Autodesk Fusion 360 part; units mm, degrees
(part 2 of 3)
ref_plane "WorkPlane125" through (0, 0, 11) normal (0, 0, 1) x (1, 0, 0)
sketch "magnet_N_st4_a3_d0" plane through (0, 0, 11) normal (0, 0, 1) x (1, 0, 0)
  line L0 (80.2, 10) -> (99.8, 10)
  line L1 (99.8, 10) -> (99.8, 20)
  line L2 (99.8, 20) -> (80.2, 20)
  line L3 (80.2, 20) -> (80.2, 10)
extrude "Extrude85" add sketch "magnet_N_st4_a3_d0" along normal mid plane 5 separate body makes body 105
ref_plane "WorkPlane126" through (0, 0, 16) normal (0, 0, 1) x (1, 0, 0)
sketch "magnet_N_st4_a3_d1" plane through (0, 0, 16) normal (0, 0, 1) x (1, 0, 0)
  line L0 (80.2, 10) -> (99.8, 10)
  line L1 (99.8, 10) -> (99.8, 20)
  line L2 (99.8, 20) -> (80.2, 20)
  line L3 (80.2, 20) -> (80.2, 10)
extrude "Extrude86" add sketch "magnet_N_st4_a3_d1" along normal mid plane 5 separate body makes body 106
ref_plane "WorkPlane127" through (0, 0, -11) normal (0, 0, 1) x (1, 0, 0)
sketch "magnet_S_st4_a3_d0" plane through (0, 0, -11) normal (0, 0, 1) x (1, 0, 0)
  line L0 (80.2, 10) -> (99.8, 10)
  line L1 (99.8, 10) -> (99.8, 20)
  line L2 (99.8, 20) -> (80.2, 20)
  line L3 (80.2, 20) -> (80.2, 10)
extrude "Extrude87" add sketch "magnet_S_st4_a3_d0" along normal mid plane 5 separate body makes body 107
ref_plane "WorkPlane128" through (0, 0, -16) normal (0, 0, 1) x (1, 0, 0)
sketch "magnet_S_st4_a3_d1" plane through (0, 0, -16) normal (0, 0, 1) x (1, 0, 0)
  line L0 (80.2, 10) -> (99.8, 10)
  line L1 (99.8, 10) -> (99.8, 20)
  line L2 (99.8, 20) -> (80.2, 20)
  line L3 (80.2, 20) -> (80.2, 10)
extrude "Extrude88" add sketch "magnet_S_st4_a3_d1" along normal mid plane 5 separate body makes body 108
ref_plane "WorkPlane129" through (0, 0, 11) normal (0, 0, 1) x (1, 0, 0)
sketch "magnet_N_st5_a0_d0" plane through (0, 0, 11) normal (0, 0, 1) x (1, 0, 0)
  line L0 (100.2, -20) -> (119.8, -20)
  line L1 (119.8, -20) -> (119.8, -10)
  line L2 (119.8, -10) -> (100.2, -10)
  line L3 (100.2, -10) -> (100.2, -20)
extrude "Extrude89" add sketch "magnet_N_st5_a0_d0" along normal mid plane 5 separate body makes body 109
ref_plane "WorkPlane130" through (0, 0, 16) normal (0, 0, 1) x (1, 0, 0)
sketch "magnet_N_st5_a0_d1" plane through (0, 0, 16) normal (0, 0, 1) x (1, 0, 0)
  line L0 (100.2, -20) -> (119.8, -20)
  line L1 (119.8, -20) -> (119.8, -10)
  line L2 (119.8, -10) -> (100.2, -10)
  line L3 (100.2, -10) -> (100.2, -20)
extrude "Extrude90" add sketch "magnet_N_st5_a0_d1" along normal mid plane 5 separate body makes body 110
ref_plane "WorkPlane131" through (0, 0, -11) normal (0, 0, 1) x (1, 0, 0)
sketch "magnet_S_st5_a0_d0" plane through (0, 0, -11) normal (0, 0, 1) x (1, 0, 0)
  line L0 (100.2, -20) -> (119.8, -20)
  line L1 (119.8, -20) -> (119.8, -10)
  line L2 (119.8, -10) -> (100.2, -10)
  line L3 (100.2, -10) -> (100.2, -20)
extrude "Extrude91" add sketch "magnet_S_st5_a0_d0" along normal mid plane 5 separate body makes body 111
ref_plane "WorkPlane132" through (0, 0, -16) normal (0, 0, 1) x (1, 0, 0)
sketch "magnet_S_st5_a0_d1" plane through (0, 0, -16) normal (0, 0, 1) x (1, 0, 0)
  line L0 (100.2, -20) -> (119.8, -20)
  line L1 (119.8, -20) -> (119.8, -10)
  line L2 (119.8, -10) -> (100.2, -10)
  line L3 (100.2, -10) -> (100.2, -20)
extrude "Extrude92" add sketch "magnet_S_st5_a0_d1" along normal mid plane 5 separate body makes body 112
ref_plane "WorkPlane133" through (0, 0, 11) normal (0, 0, 1) x (1, 0, 0)
sketch "magnet_N_st5_a1_d0" plane through (0, 0, 11) normal (0, 0, 1) x (1, 0, 0)
  line L0 (100.2, -10) -> (119.8, -10)
  line L1 (119.8, -10) -> (119.8, 0)
  line L2 (119.8, 0) -> (100.2, 0)
  line L3 (100.2, 0) -> (100.2, -10)
extrude "Extrude93" add sketch "magnet_N_st5_a1_d0" along normal mid plane 5 separate body makes body 113
ref_plane "WorkPlane134" through (0, 0, 16) normal (0, 0, 1) x (1, 0, 0)
sketch "magnet_N_st5_a1_d1" plane through (0, 0, 16) normal (0, 0, 1) x (1, 0, 0)
  line L0 (100.2, -10) -> (119.8, -10)
  line L1 (119.8, -10) -> (119.8, 0)
  line L2 (119.8, 0) -> (100.2, 0)
  line L3 (100.2, 0) -> (100.2, -10)
extrude "Extrude94" add sketch "magnet_N_st5_a1_d1" along normal mid plane 5 separate body makes body 114
ref_plane "WorkPlane135" through (0, 0, -11) normal (0, 0, 1) x (1, 0, 0)
sketch "magnet_S_st5_a1_d0" plane through (0, 0, -11) normal (0, 0, 1) x (1, 0, 0)
  line L0 (100.2, -10) -> (119.8, -10)
  line L1 (119.8, -10) -> (119.8, 0)
  line L2 (119.8, 0) -> (100.2, 0)
  line L3 (100.2, 0) -> (100.2, -10)
extrude "Extrude95" add sketch "magnet_S_st5_a1_d0" along normal mid plane 5 separate body makes body 115
ref_plane "WorkPlane136" through (0, 0, -16) normal (0, 0, 1) x (1, 0, 0)
sketch "magnet_S_st5_a1_d1" plane through (0, 0, -16) normal (0, 0, 1) x (1, 0, 0)
  line L0 (100.2, -10) -> (119.8, -10)
  line L1 (119.8, -10) -> (119.8, 0)
  line L2 (119.8, 0) -> (100.2, 0)
  line L3 (100.2, 0) -> (100.2, -10)
extrude "Extrude96" add sketch "magnet_S_st5_a1_d1" along normal mid plane 5 separate body makes body 116
ref_plane "WorkPlane137" through (0, 0, 11) normal (0, 0, 1) x (1, 0, 0)
sketch "magnet_N_st5_a2_d0" plane through (0, 0, 11) normal (0, 0, 1) x (1, 0, 0)
  line L0 (100.2, 0) -> (119.8, 0)
  line L1 (119.8, 0) -> (119.8, 10)
  line L2 (119.8, 10) -> (100.2, 10)
  line L3 (100.2, 10) -> (100.2, 0)
extrude "Extrude97" add sketch "magnet_N_st5_a2_d0" along normal mid plane 5 separate body makes body 117
ref_plane "WorkPlane138" through (0, 0, 16) normal (0, 0, 1) x (1, 0, 0)
sketch "magnet_N_st5_a2_d1" plane through (0, 0, 16) normal (0, 0, 1) x (1, 0, 0)
  line L0 (100.2, 0) -> (119.8, 0)
  line L1 (119.8, 0) -> (119.8, 10)
  line L2 (119.8, 10) -> (100.2, 10)
  line L3 (100.2, 10) -> (100.2, 0)
extrude "Extrude98" add sketch "magnet_N_st5_a2_d1" along normal mid plane 5 separate body makes body 118
ref_plane "WorkPlane139" through (0, 0, -11) normal (0, 0, 1) x (1, 0, 0)
sketch "magnet_S_st5_a2_d0" plane through (0, 0, -11) normal (0, 0, 1) x (1, 0, 0)
  line L0 (100.2, 0) -> (119.8, 0)
  line L1 (119.8, 0) -> (119.8, 10)
  line L2 (119.8, 10) -> (100.2, 10)
  line L3 (100.2, 10) -> (100.2, 0)
extrude "Extrude99" add sketch "magnet_S_st5_a2_d0" along normal mid plane 5 separate body makes body 119
ref_plane "WorkPlane140" through (0, 0, -16) normal (0, 0, 1) x (1, 0, 0)
sketch "magnet_S_st5_a2_d1" plane through (0, 0, -16) normal (0, 0, 1) x (1, 0, 0)
  line L0 (100.2, 0) -> (119.8, 0)
  line L1 (119.8, 0) -> (119.8, 10)
  line L2 (119.8, 10) -> (100.2, 10)
  line L3 (100.2, 10) -> (100.2, 0)
extrude "Extrude100" add sketch "magnet_S_st5_a2_d1" along normal mid plane 5 separate body makes body 120
ref_plane "WorkPlane141" through (0, 0, 11) normal (0, 0, 1) x (1, 0, 0)
sketch "magnet_N_st5_a3_d0" plane through (0, 0, 11) normal (0, 0, 1) x (1, 0, 0)
  line L0 (100.2, 10) -> (119.8, 10)
  line L1 (119.8, 10) -> (119.8, 20)
  line L2 (119.8, 20) -> (100.2, 20)
  line L3 (100.2, 20) -> (100.2, 10)
extrude "Extrude101" add sketch "magnet_N_st5_a3_d0" along normal mid plane 5 separate body makes body 121
ref_plane "WorkPlane142" through (0, 0, 16) normal (0, 0, 1) x (1, 0, 0)
sketch "magnet_N_st5_a3_d1" plane through (0, 0, 16) normal (0, 0, 1) x (1, 0, 0)
  line L0 (100.2, 10) -> (119.8, 10)
  line L1 (119.8, 10) -> (119.8, 20)
  line L2 (119.8, 20) -> (100.2, 20)
  line L3 (100.2, 20) -> (100.2, 10)
extrude "Extrude102" add sketch "magnet_N_st5_a3_d1" along normal mid plane 5 separate body makes body 122
ref_plane "WorkPlane143" through (0, 0, -11) normal (0, 0, 1) x (1, 0, 0)
sketch "magnet_S_st5_a3_d0" plane through (0, 0, -11) normal (0, 0, 1) x (1, 0, 0)
  line L0 (100.2, 10) -> (119.8, 10)
  line L1 (119.8, 10) -> (119.8, 20)
  line L2 (119.8, 20) -> (100.2, 20)
  line L3 (100.2, 20) -> (100.2, 10)
extrude "Extrude103" add sketch "magnet_S_st5_a3_d0" along normal mid plane 5 separate body makes body 123
ref_plane "WorkPlane144" through (0, 0, -16) normal (0, 0, 1) x (1, 0, 0)
sketch "magnet_S_st5_a3_d1" plane through (0, 0, -16) normal (0, 0, 1) x (1, 0, 0)
  line L0 (100.2, 10) -> (119.8, 10)
  line L1 (119.8, 10) -> (119.8, 20)
  line L2 (119.8, 20) -> (100.2, 20)
  line L3 (100.2, 20) -> (100.2, 10)
extrude "Extrude104" add sketch "magnet_S_st5_a3_d1" along normal mid plane 5 separate body makes body 124
ref_plane "WorkPlane145" through (0, 0, 19.5) normal (0, 0, 1) x (1, 0, 0)
sketch "hood_top" plane through (0, 0, 19.5) normal (0, 0, 1) x (1, 0, 0)
  line L0 (-1, -26) -> (121, -26)
  line L1 (121, -26) -> (121, 26)
  line L2 (121, 26) -> (-1, 26)
  line L3 (-1, 26) -> (-1, -26)
extrude "Extrude105" add sketch "hood_top" along normal mid plane 2 separate body makes body 125
ref_plane "WorkPlane146" through (0, 0, -19.5) normal (0, 0, 1) x (1, 0, 0)
sketch "hood_bottom" plane through (0, 0, -19.5) normal (0, 0, 1) x (1, 0, 0)
  line L0 (-1, -26) -> (121, -26)
  line L1 (121, -26) -> (121, 26)
  line L2 (121, 26) -> (-1, 26)
  line L3 (-1, 26) -> (-1, -26)
extrude "Extrude106" add sketch "hood_bottom" along normal mid plane 2 separate body makes body 126
ref_plane "WorkPlane147" through (0, 24.5, 0) normal (0, 1, 0) x (0, 0, 1)
sketch "endbar_rear_p" plane through (0, 24.5, 0) normal (0, 1, 0) x (1, 0, 0)
  line L0 (118, -18.5) -> (120, -18.5)
  line L1 (120, -18.5) -> (120, 18.5)
  line L2 (120, 18.5) -> (118, 18.5)
  line L3 (118, 18.5) -> (118, -18.5)
extrude "Extrude107" add sketch "endbar_rear_p" along normal mid plane 2 separate body makes body 127
ref_plane "WorkPlane148" through (0, -24.5, 0) normal (0, 1, 0) x (0, 0, 1)
sketch "endbar_rear_n" plane through (0, -24.5, 0) normal (0, 1, 0) x (1, 0, 0)
  line L0 (118, -18.5) -> (120, -18.5)
  line L1 (120, -18.5) -> (120, 18.5)
  line L2 (120, 18.5) -> (118, 18.5)
  line L3 (118, 18.5) -> (118, -18.5)
extrude "Extrude108" add sketch "endbar_rear_n" along normal mid plane 2 separate body makes body 128
ref_plane "WorkPlane149" through (-30, 0, 0) normal (1, 0, 0) x (0, 1, 0)
sketch "Sketch149" plane through (-30, 0, 0) normal (1, 0, 0) x (0, 0, -1)
  line L0 (-12.2, -25.2) -> (-11, -25.2)
  line L1 (-11, -25.2) -> (-11, 25.2)
  line L2 (-11, 25.2) -> (-12.2, 25.2)
  line L3 (-12.2, 25.2) -> (-12.2, -25.2)
ref_plane "WorkPlane150" through (-23.6, 0, 0) normal (1, 0, 0) x (0, 1, 0)
sketch "Sketch150" plane through (-23.6, 0, 0) normal (1, 0, 0) x (0, 0, -1)
  line L0 (-17.346, -29.146) -> (-13.8, -29.146)
  line L1 (-13.8, -29.146) -> (-13.8, 29.146)
  line L2 (-13.8, 29.146) -> (-17.346, 29.146)
  line L3 (-17.346, 29.146) -> (-17.346, -29.146)
loft "Loft21" add profiles "Sketch149", "Sketch150" section 1 section 2 separate body makes body 129
ref_plane "WorkPlane151" through (-24.4, 0, 0) normal (1, 0, 0) x (0, 1, 0)
sketch "Sketch151" plane through (-24.4, 0, 0) normal (1, 0, 0) x (0, 0, -1)
  line L0 (-16.8608, -28.8108) -> (-13.45, -28.8108)
  line L1 (-13.45, -28.8108) -> (-13.45, 28.8108)
  line L2 (-13.45, 28.8108) -> (-16.8608, 28.8108)
  line L3 (-16.8608, 28.8108) -> (-16.8608, -28.8108)
ref_plane "WorkPlane152" through (-21.6, 0, 0) normal (1, 0, 0) x (0, 1, 0)
sketch "Sketch152" plane through (-21.6, 0, 0) normal (1, 0, 0) x (0, 0, -1)
  line L0 (-18.4462, -29.8371) -> (-14.6091, -29.8371)
  line L1 (-14.6091, -29.8371) -> (-14.6091, 29.8371)
  line L2 (-14.6091, 29.8371) -> (-18.4462, 29.8371)
  line L3 (-18.4462, 29.8371) -> (-18.4462, -29.8371)
loft "Loft22" add profiles "Sketch151", "Sketch152" section 1 section 2 separate body makes body 130
ref_plane "WorkPlane153" through (-22.4, 0, 0) normal (1, 0, 0) x (0, 1, 0)
sketch "Sketch153" plane through (-22.4, 0, 0) normal (1, 0, 0) x (0, 0, -1)
  line L0 (-18.0528, -29.6278) -> (-14.325, -29.6278)
  line L1 (-14.325, -29.6278) -> (-14.325, 29.6278)
  line L2 (-14.325, 29.6278) -> (-18.0528, 29.6278)
  line L3 (-18.0528, 29.6278) -> (-18.0528, -29.6278)
ref_plane "WorkPlane154" through (-17.6, 0, 0) normal (1, 0, 0) x (0, 1, 0)
sketch "Sketch154" plane through (-17.6, 0, 0) normal (1, 0, 0) x (0, 0, -1)
  line L0 (-19.9773, -30.2773) -> (-15.7, -30.2773)
  line L1 (-15.7, -30.2773) -> (-15.7, 30.2773)
  line L2 (-15.7, 30.2773) -> (-19.9773, 30.2773)
  line L3 (-19.9773, 30.2773) -> (-19.9773, -30.2773)
loft "Loft23" add profiles "Sketch153", "Sketch154" section 1 section 2 separate body makes body 131
ref_plane "WorkPlane155" through (-18.4, 0, 0) normal (1, 0, 0) x (0, 1, 0)
sketch "Sketch155" plane through (-18.4, 0, 0) normal (1, 0, 0) x (0, 0, -1)
  line L0 (-19.6832, -30.2013) -> (-15.4818, -30.2013)
  line L1 (-15.4818, -30.2013) -> (-15.4818, 30.2013)
  line L2 (-15.4818, 30.2013) -> (-19.6832, 30.2013)
  line L3 (-19.6832, 30.2013) -> (-19.6832, -30.2013)
ref_plane "WorkPlane156" through (-11.6, 0, 0) normal (1, 0, 0) x (0, 1, 0)
sketch "Sketch156" plane through (-11.6, 0, 0) normal (1, 0, 0) x (0, 0, -1)
  line L0 (-22.0408, -30.7044) -> (-17.3364, -30.7044)
  line L1 (-17.3364, -30.7044) -> (-17.3364, 30.7044)
  line L2 (-17.3364, 30.7044) -> (-22.0408, 30.7044)
  line L3 (-22.0408, 30.7044) -> (-22.0408, -30.7044)
loft "Loft24" add profiles "Sketch155", "Sketch156" section 1 section 2 separate body makes body 132
ref_plane "WorkPlane157" through (-12.4, 0, 0) normal (1, 0, 0) x (0, 1, 0)
sketch "Sketch157" plane through (-12.4, 0, 0) normal (1, 0, 0) x (0, 0, -1)
  line L0 (-21.7784, -30.6602) -> (-17.1182, -30.6602)
  line L1 (-17.1182, -30.6602) -> (-17.1182, 30.6602)
  line L2 (-17.1182, 30.6602) -> (-21.7784, 30.6602)
  line L3 (-21.7784, 30.6602) -> (-21.7784, -30.6602)
ref_plane "WorkPlane158" through (-5.6, 0, 0) normal (1, 0, 0) x (0, 1, 0)
sketch "Sketch158" plane through (-5.6, 0, 0) normal (1, 0, 0) x (0, 0, -1)
  line L0 (-23.9059, -30.9332) -> (-18.9727, -30.9332)
  line L1 (-18.9727, -30.9332) -> (-18.9727, 30.9332)
  line L2 (-18.9727, 30.9332) -> (-23.9059, 30.9332)
  line L3 (-23.9059, 30.9332) -> (-23.9059, -30.9332)
loft "Loft25" add profiles "Sketch157", "Sketch158" section 1 section 2 separate body makes body 133
ref_plane "WorkPlane159" through (-6.4, 0, 0) normal (1, 0, 0) x (0, 1, 0)
sketch "Sketch159" plane through (-6.4, 0, 0) normal (1, 0, 0) x (0, 0, -1)
  line L0 (-23.6671, -30.9125) -> (-18.7545, -30.9125)
  line L1 (-18.7545, -30.9125) -> (-18.7545, 30.9125)
  line L2 (-18.7545, 30.9125) -> (-23.6671, 30.9125)
  line L3 (-23.6671, 30.9125) -> (-23.6671, -30.9125)
ref_plane "WorkPlane160" through (0.4, 0, 0) normal (1, 0, 0) x (0, 1, 0)
sketch "Sketch160" plane through (0.4, 0, 0) normal (1, 0, 0) x (0, 0, -1)
  line L0 (-25.5, -31) -> (-20.5, -31)
  line L1 (-20.5, -31) -> (-20.5, 31)
  line L2 (-20.5, 31) -> (-25.5, 31)
  line L3 (-25.5, 31) -> (-25.5, -31)
loft "Loft26" add profiles "Sketch159", "Sketch160" section 1 section 2 separate body makes body 134
ref_plane "WorkPlane161" through (-0.4, 0, 0) normal (1, 0, 0) x (0, 1, 0)
sketch "Sketch161" plane through (-0.4, 0, 0) normal (1, 0, 0) x (0, 0, -1)
  line L0 (-25.3906, -30.9997) -> (-20.3909, -30.9997)
  line L1 (-20.3909, -30.9997) -> (-20.3909, 30.9997)
  line L2 (-20.3909, 30.9997) -> (-25.3906, 30.9997)
  line L3 (-25.3906, 30.9997) -> (-25.3906, -30.9997)
ref_plane "WorkPlane162" through (30.4, 0, 0) normal (1, 0, 0) x (0, 1, 0)
sketch "Sketch162" plane through (30.4, 0, 0) normal (1, 0, 0) x (0, 0, -1)
  line L0 (-25.5, -31) -> (-20.5, -31)
  line L1 (-20.5, -31) -> (-20.5, 31)
  line L2 (-20.5, 31) -> (-25.5, 31)
  line L3 (-25.5, 31) -> (-25.5, -31)
loft "Loft27" add profiles "Sketch161", "Sketch162" section 1 section 2 separate body makes body 135
ref_plane "WorkPlane163" through (29.6, 0, 0) normal (1, 0, 0) x (0, 1, 0)
sketch "Sketch163" plane through (29.6, 0, 0) normal (1, 0, 0) x (0, 0, -1)
  line L0 (-25.5, -31) -> (-20.5, -31)
  line L1 (-20.5, -31) -> (-20.5, 31)
  line L2 (-20.5, 31) -> (-25.5, 31)
  line L3 (-25.5, 31) -> (-25.5, -31)
ref_plane "WorkPlane164" through (60.4, 0, 0) normal (1, 0, 0) x (0, 1, 0)
sketch "Sketch164" plane through (60.4, 0, 0) normal (1, 0, 0) x (0, 0, -1)
  line L0 (-25.5, -31) -> (-20.5, -31)
  line L1 (-20.5, -31) -> (-20.5, 31)
  line L2 (-20.5, 31) -> (-25.5, 31)
  line L3 (-25.5, 31) -> (-25.5, -31)
loft "Loft28" add profiles "Sketch163", "Sketch164" section 1 section 2 separate body makes body 136
ref_plane "WorkPlane165" through (59.6, 0, 0) normal (1, 0, 0) x (0, 1, 0)
sketch "Sketch165" plane through (59.6, 0, 0) normal (1, 0, 0) x (0, 0, -1)
  line L0 (-25.5, -31) -> (-20.5, -31)
  line L1 (-20.5, -31) -> (-20.5, 31)
  line L2 (-20.5, 31) -> (-25.5, 31)
  line L3 (-25.5, 31) -> (-25.5, -31)
ref_plane "WorkPlane166" through (90.4, 0, 0) normal (1, 0, 0) x (0, 1, 0)
sketch "Sketch166" plane through (90.4, 0, 0) normal (1, 0, 0) x (0, 0, -1)
  line L0 (-25.5, -31) -> (-20.5, -31)
  line L1 (-20.5, -31) -> (-20.5, 31)
  line L2 (-20.5, 31) -> (-25.5, 31)
  line L3 (-25.5, 31) -> (-25.5, -31)
loft "Loft29" add profiles "Sketch165", "Sketch166" section 1 section 2 separate body makes body 137
ref_plane "WorkPlane167" through (89.6, 0, 0) normal (1, 0, 0) x (0, 1, 0)
sketch "Sketch167" plane through (89.6, 0, 0) normal (1, 0, 0) x (0, 0, -1)
  line L0 (-25.5, -31) -> (-20.5, -31)
  line L1 (-20.5, -31) -> (-20.5, 31)
  line L2 (-20.5, 31) -> (-25.5, 31)
  line L3 (-25.5, 31) -> (-25.5, -31)
ref_plane "WorkPlane168" through (120.4, 0, 0) normal (1, 0, 0) x (0, 1, 0)
sketch "Sketch168" plane through (120.4, 0, 0) normal (1, 0, 0) x (0, 0, -1)
  line L0 (-25.4848, -30.9848) -> (-20.5, -30.9848)
  line L1 (-20.5, -30.9848) -> (-20.5, 30.9848)
  line L2 (-20.5, 30.9848) -> (-25.4848, 30.9848)
  line L3 (-25.4848, 30.9848) -> (-25.4848, -30.9848)
loft "Loft30" add profiles "Sketch167", "Sketch168" section 1 section 2 separate body makes body 138
ref_plane "WorkPlane169" through (119.6, 0, 0) normal (1, 0, 0) x (0, 1, 0)
sketch "Sketch169" plane through (119.6, 0, 0) normal (1, 0, 0) x (0, 0, -1)
  line L0 (-25.5, -31) -> (-20.5, -31)
  line L1 (-20.5, -31) -> (-20.5, 31)
  line L2 (-20.5, 31) -> (-25.5, 31)
  line L3 (-25.5, 31) -> (-25.5, -31)
ref_plane "WorkPlane170" through (122.4, 0, 0) normal (1, 0, 0) x (0, 1, 0)
sketch "Sketch170" plane through (122.4, 0, 0) normal (1, 0, 0) x (0, 0, -1)
  line L0 (-25.323, -30.8142) -> (-20.4147, -30.8142)
  line L1 (-20.4147, -30.8142) -> (-20.4147, 30.8142)
  line L2 (-20.4147, 30.8142) -> (-25.323, 30.8142)
  line L3 (-25.323, 30.8142) -> (-25.323, -30.8142)
loft "Loft31" add profiles "Sketch169", "Sketch170" section 1 section 2 separate body makes body 139
ref_plane "WorkPlane171" through (121.6, 0, 0) normal (1, 0, 0) x (0, 1, 0)
sketch "Sketch171" plane through (121.6, 0, 0) normal (1, 0, 0) x (0, 0, -1)
  line L0 (-25.439, -30.939) -> (-20.5, -30.939)
  line L1 (-20.5, -30.939) -> (-20.5, 30.939)
  line L2 (-20.5, 30.939) -> (-25.439, 30.939)
  line L3 (-25.439, 30.939) -> (-25.439, -30.939)
ref_plane "WorkPlane172" through (132.0667, 0, 0) normal (1, 0, 0) x (0, 1, 0)
sketch "Sketch172" plane through (132.0667, 0, 0) normal (1, 0, 0) x (0, 0, -1)
  line L0 (-22.8821, -28.16) -> (-18.3534, -28.16)
  line L1 (-18.3534, -28.16) -> (-18.3534, 28.16)
  line L2 (-18.3534, 28.16) -> (-22.8821, 28.16)
  line L3 (-22.8821, 28.16) -> (-22.8821, -28.16)
loft "Loft32" add profiles "Sketch171", "Sketch172" section 1 section 2 separate body makes body 140
ref_plane "WorkPlane173" through (131.2667, 0, 0) normal (1, 0, 0) x (0, 1, 0)
sketch "Sketch173" plane through (131.2667, 0, 0) normal (1, 0, 0) x (0, 0, -1)
  line L0 (-23.0848, -28.3803) -> (-18.524, -28.3803)
  line L1 (-18.524, -28.3803) -> (-18.524, 28.3803)
  line L2 (-18.524, 28.3803) -> (-23.0848, 28.3803)
  line L3 (-23.0848, 28.3803) -> (-23.0848, -28.3803)
ref_plane "WorkPlane174" through (143.7333, 0, 0) normal (1, 0, 0) x (0, 1, 0)
sketch "Sketch174" plane through (143.7333, 0, 0) normal (1, 0, 0) x (0, 0, -1)
  line L0 (-19.9095, -24.9301) -> (-15.8657, -24.9301)
  line L1 (-15.8657, -24.9301) -> (-15.8657, 24.9301)
  line L2 (-15.8657, 24.9301) -> (-19.9095, 24.9301)
  line L3 (-19.9095, 24.9301) -> (-19.9095, -24.9301)
loft "Loft33" add profiles "Sketch173", "Sketch174" section 1 section 2 separate body makes body 141
ref_plane "WorkPlane175" through (142.9333, 0, 0) normal (1, 0, 0) x (0, 1, 0)
sketch "Sketch175" plane through (142.9333, 0, 0) normal (1, 0, 0) x (0, 0, -1)
  line L0 (-20.1144, -25.1527) -> (-16.0363, -25.1527)
  line L1 (-16.0363, -25.1527) -> (-16.0363, 25.1527)
  line L2 (-16.0363, 25.1527) -> (-20.1144, 25.1527)
  line L3 (-20.1144, 25.1527) -> (-20.1144, -25.1527)
ref_plane "WorkPlane176" through (155.4, 0, 0) normal (1, 0, 0) x (0, 1, 0)
sketch "Sketch176" plane through (155.4, 0, 0) normal (1, 0, 0) x (0, 0, -1)
  line L0 (-16.8984, -21.6616) -> (-13.3779, -21.6616)
  line L1 (-13.3779, -21.6616) -> (-13.3779, 21.6616)
  line L2 (-13.3779, 21.6616) -> (-16.8984, 21.6616)
  line L3 (-16.8984, 21.6616) -> (-16.8984, -21.6616)
loft "Loft34" add profiles "Sketch175", "Sketch176" section 1 section 2 separate body makes body 142
ref_plane "WorkPlane177" through (154.6, 0, 0) normal (1, 0, 0) x (0, 1, 0)
sketch "Sketch177" plane through (154.6, 0, 0) normal (1, 0, 0) x (0, 0, -1)
  line L0 (-17.1064, -21.8873) -> (-13.5485, -21.8873)
  line L1 (-13.5485, -21.8873) -> (-13.5485, 21.8873)
  line L2 (-13.5485, 21.8873) -> (-17.1064, 21.8873)
  line L3 (-17.1064, 21.8873) -> (-17.1064, -21.8873)
ref_plane "WorkPlane178" through (167.0667, 0, 0) normal (1, 0, 0) x (0, 1, 0)
sketch "Sketch178" plane through (167.0667, 0, 0) normal (1, 0, 0) x (0, 0, -1)
  line L0 (-13.8302, -18.336) -> (-10.8902, -18.336)
  line L1 (-10.8902, -18.336) -> (-10.8902, 18.336)
  line L2 (-10.8902, 18.336) -> (-13.8302, 18.336)
  line L3 (-13.8302, 18.336) -> (-13.8302, -18.336)
loft "Loft35" add profiles "Sketch177", "Sketch178" section 1 section 2 separate body makes body 143
ref_plane "WorkPlane179" through (166.2667, 0, 0) normal (1, 0, 0) x (0, 1, 0)
sketch "Sketch179" plane through (166.2667, 0, 0) normal (1, 0, 0) x (0, 0, -1)
  line L0 (-14.043, -18.5666) -> (-11.0608, -18.5666)
  line L1 (-11.0608, -18.5666) -> (-11.0608, 18.5666)
  line L2 (-11.0608, 18.5666) -> (-14.043, 18.5666)
  line L3 (-14.043, 18.5666) -> (-14.043, -18.5666)
ref_plane "WorkPlane180" through (178.7333, 0, 0) normal (1, 0, 0) x (0, 1, 0)
sketch "Sketch180" plane through (178.7333, 0, 0) normal (1, 0, 0) x (0, 0, -1)
  line L0 (-10.6604, -14.9089) -> (-8.4025, -14.9089)
  line L1 (-8.4025, -14.9089) -> (-8.4025, 14.9089)
  line L2 (-8.4025, 14.9089) -> (-10.6604, 14.9089)
  line L3 (-10.6604, 14.9089) -> (-10.6604, -14.9089)
loft "Loft36" add profiles "Sketch179", "Sketch180" section 1 section 2 separate body makes body 144
ref_plane "WorkPlane181" through (177.9333, 0, 0) normal (1, 0, 0) x (0, 1, 0)
sketch "Sketch181" plane through (177.9333, 0, 0) normal (1, 0, 0) x (0, 0, -1)
  line L0 (-10.883, -15.1492) -> (-8.573, -15.1492)
  line L1 (-8.573, -15.1492) -> (-8.573, 15.1492)
  line L2 (-8.573, 15.1492) -> (-10.883, 15.1492)
  line L3 (-10.883, 15.1492) -> (-10.883, -15.1492)
ref_plane "WorkPlane182" through (190, 0, 0) normal (1, 0, 0) x (0, 1, 0)
sketch "Sketch182" plane through (190, 0, 0) normal (1, 0, 0) x (0, 0, -1)
  line L0 (-7.2, -11.2) -> (-6, -11.2)
  line L1 (-6, -11.2) -> (-6, 11.2)
  line L2 (-6, 11.2) -> (-7.2, 11.2)
  line L3 (-7.2, 11.2) -> (-7.2, -11.2)
loft "Loft37" add profiles "Sketch181", "Sketch182" section 1 section 2 separate body makes body 145
ref_plane "WorkPlane183" through (-30, 0, 0) normal (1, 0, 0) x (0, 1, 0)
sketch "Sketch183" plane through (-30, 0, 0) normal (1, 0, 0) x (0, 0, -1)
  line L0 (11, -25.2) -> (12.2, -25.2)
  line L1 (12.2, -25.2) -> (12.2, 25.2)
  line L2 (12.2, 25.2) -> (11, 25.2)
  line L3 (11, 25.2) -> (11, -25.2)
ref_plane "WorkPlane184" through (-23.6, 0, 0) normal (1, 0, 0) x (0, 1, 0)
sketch "Sketch184" plane through (-23.6, 0, 0) normal (1, 0, 0) x (0, 0, -1)
  line L0 (13.8, -29.146) -> (17.346, -29.146)
  line L1 (17.346, -29.146) -> (17.346, 29.146)
  line L2 (17.346, 29.146) -> (13.8, 29.146)
  line L3 (13.8, 29.146) -> (13.8, -29.146)
loft "Loft38" add profiles "Sketch183", "Sketch184" section 1 section 2 separate body makes body 146
ref_plane "WorkPlane185" through (-24.4, 0, 0) normal (1, 0, 0) x (0, 1, 0)
sketch "Sketch185" plane through (-24.4, 0, 0) normal (1, 0, 0) x (0, 0, -1)
  line L0 (13.45, -28.8108) -> (16.8608, -28.8108)
  line L1 (16.8608, -28.8108) -> (16.8608, 28.8108)
  line L2 (16.8608, 28.8108) -> (13.45, 28.8108)
  line L3 (13.45, 28.8108) -> (13.45, -28.8108)
ref_plane "WorkPlane186" through (-21.6, 0, 0) normal (1, 0, 0) x (0, 1, 0)
sketch "Sketch186" plane through (-21.6, 0, 0) normal (1, 0, 0) x (0, 0, -1)
  line L0 (14.6091, -29.8371) -> (18.4462, -29.8371)
  line L1 (18.4462, -29.8371) -> (18.4462, 29.8371)
  line L2 (18.4462, 29.8371) -> (14.6091, 29.8371)
  line L3 (14.6091, 29.8371) -> (14.6091, -29.8371)
loft "Loft39" add profiles "Sketch185", "Sketch186" section 1 section 2 separate body makes body 147
ref_plane "WorkPlane187" through (-22.4, 0, 0) normal (1, 0, 0) x (0, 1, 0)
sketch "Sketch187" plane through (-22.4, 0, 0) normal (1, 0, 0) x (0, 0, -1)
  line L0 (14.325, -29.6278) -> (18.0528, -29.6278)
  line L1 (18.0528, -29.6278) -> (18.0528, 29.6278)
  line L2 (18.0528, 29.6278) -> (14.325, 29.6278)
  line L3 (14.325, 29.6278) -> (14.325, -29.6278)
ref_plane "WorkPlane188" through (-17.6, 0, 0) normal (1, 0, 0) x (0, 1, 0)
sketch "Sketch188" plane through (-17.6, 0, 0) normal (1, 0, 0) x (0, 0, -1)
  line L0 (15.7, -30.2773) -> (19.9773, -30.2773)
  line L1 (19.9773, -30.2773) -> (19.9773, 30.2773)
  line L2 (19.9773, 30.2773) -> (15.7, 30.2773)
  line L3 (15.7, 30.2773) -> (15.7, -30.2773)
loft "Loft40" add profiles "Sketch187", "Sketch188" section 1 section 2 separate body makes body 148
ref_plane "WorkPlane189" through (-18.4, 0, 0) normal (1, 0, 0) x (0, 1, 0)
sketch "Sketch189" plane through (-18.4, 0, 0) normal (1, 0, 0) x (0, 0, -1)
  line L0 (15.4818, -30.2013) -> (19.6832, -30.2013)
  line L1 (19.6832, -30.2013) -> (19.6832, 30.2013)
  line L2 (19.6832, 30.2013) -> (15.4818, 30.2013)
  line L3 (15.4818, 30.2013) -> (15.4818, -30.2013)
ref_plane "WorkPlane190" through (-11.6, 0, 0) normal (1, 0, 0) x (0, 1, 0)
sketch "Sketch190" plane through (-11.6, 0, 0) normal (1, 0, 0) x (0, 0, -1)
  line L0 (17.3364, -30.7044) -> (22.0408, -30.7044)
  line L1 (22.0408, -30.7044) -> (22.0408, 30.7044)
  line L2 (22.0408, 30.7044) -> (17.3364, 30.7044)
  line L3 (17.3364, 30.7044) -> (17.3364, -30.7044)
loft "Loft41" add profiles "Sketch189", "Sketch190" section 1 section 2 separate body makes body 149
ref_plane "WorkPlane191" through (-12.4, 0, 0) normal (1, 0, 0) x (0, 1, 0)
sketch "Sketch191" plane through (-12.4, 0, 0) normal (1, 0, 0) x (0, 0, -1)
  line L0 (17.1182, -30.6602) -> (21.7784, -30.6602)
  line L1 (21.7784, -30.6602) -> (21.7784, 30.6602)
  line L2 (21.7784, 30.6602) -> (17.1182, 30.6602)
  line L3 (17.1182, 30.6602) -> (17.1182, -30.6602)
ref_plane "WorkPlane192" through (-5.6, 0, 0) normal (1, 0, 0) x (0, 1, 0)
sketch "Sketch192" plane through (-5.6, 0, 0) normal (1, 0, 0) x (0, 0, -1)
  line L0 (18.9727, -30.9332) -> (23.9059, -30.9332)
  line L1 (23.9059, -30.9332) -> (23.9059, 30.9332)
  line L2 (23.9059, 30.9332) -> (18.9727, 30.9332)
  line L3 (18.9727, 30.9332) -> (18.9727, -30.9332)
loft "Loft42" add profiles "Sketch191", "Sketch192" section 1 section 2 separate body makes body 150
ref_plane "WorkPlane193" through (-6.4, 0, 0) normal (1, 0, 0) x (0, 1, 0)
sketch "Sketch193" plane through (-6.4, 0, 0) normal (1, 0, 0) x (0, 0, -1)
  line L0 (18.7545, -30.9125) -> (23.6671, -30.9125)
  line L1 (23.6671, -30.9125) -> (23.6671, 30.9125)
  line L2 (23.6671, 30.9125) -> (18.7545, 30.9125)
  line L3 (18.7545, 30.9125) -> (18.7545, -30.9125)
ref_plane "WorkPlane194" through (0.4, 0, 0) normal (1, 0, 0) x (0, 1, 0)
sketch "Sketch194" plane through (0.4, 0, 0) normal (1, 0, 0) x (0, 0, -1)
  line L0 (20.5, -31) -> (25.5, -31)
  line L1 (25.5, -31) -> (25.5, 31)
  line L2 (25.5, 31) -> (20.5, 31)
  line L3 (20.5, 31) -> (20.5, -31)
loft "Loft43" add profiles "Sketch193", "Sketch194" section 1 section 2 separate body makes body 151
ref_plane "WorkPlane195" through (-0.4, 0, 0) normal (1, 0, 0) x (0, 1, 0)
sketch "Sketch195" plane through (-0.4, 0, 0) normal (1, 0, 0) x (0, 0, -1)
  line L0 (20.3909, -30.9997) -> (25.3906, -30.9997)
  line L1 (25.3906, -30.9997) -> (25.3906, 30.9997)
  line L2 (25.3906, 30.9997) -> (20.3909, 30.9997)
  line L3 (20.3909, 30.9997) -> (20.3909, -30.9997)
ref_plane "WorkPlane196" through (30.4, 0, 0) normal (1, 0, 0) x (0, 1, 0)
sketch "Sketch196" plane through (30.4, 0, 0) normal (1, 0, 0) x (0, 0, -1)
  line L0 (20.5, -31) -> (25.5, -31)
  line L1 (25.5, -31) -> (25.5, 31)
  line L2 (25.5, 31) -> (20.5, 31)
  line L3 (20.5, 31) -> (20.5, -31)
loft "Loft44" add profiles "Sketch195", "Sketch196" section 1 section 2 separate body makes body 152
ref_plane "WorkPlane197" through (29.6, 0, 0) normal (1, 0, 0) x (0, 1, 0)
sketch "Sketch197" plane through (29.6, 0, 0) normal (1, 0, 0) x (0, 0, -1)
  line L0 (20.5, -31) -> (25.5, -31)
  line L1 (25.5, -31) -> (25.5, 31)
  line L2 (25.5, 31) -> (20.5, 31)
  line L3 (20.5, 31) -> (20.5, -31)
ref_plane "WorkPlane198" through (60.4, 0, 0) normal (1, 0, 0) x (0, 1, 0)
sketch "Sketch198" plane through (60.4, 0, 0) normal (1, 0, 0) x (0, 0, -1)
  line L0 (20.5, -31) -> (25.5, -31)
  line L1 (25.5, -31) -> (25.5, 31)
  line L2 (25.5, 31) -> (20.5, 31)
  line L3 (20.5, 31) -> (20.5, -31)
loft "Loft45" add profiles "Sketch197", "Sketch198" section 1 section 2 separate body makes body 153
ref_plane "WorkPlane199" through (59.6, 0, 0) normal (1, 0, 0) x (0, 1, 0)
sketch "Sketch199" plane through (59.6, 0, 0) normal (1, 0, 0) x (0, 0, -1)
  line L0 (20.5, -31) -> (25.5, -31)
  line L1 (25.5, -31) -> (25.5, 31)
  line L2 (25.5, 31) -> (20.5, 31)
  line L3 (20.5, 31) -> (20.5, -31)
ref_plane "WorkPlane200" through (90.4, 0, 0) normal (1, 0, 0) x (0, 1, 0)
sketch "Sketch200" plane through (90.4, 0, 0) normal (1, 0, 0) x (0, 0, -1)
  line L0 (20.5, -31) -> (25.5, -31)
  line L1 (25.5, -31) -> (25.5, 31)
  line L2 (25.5, 31) -> (20.5, 31)
  line L3 (20.5, 31) -> (20.5, -31)
loft "Loft46" add profiles "Sketch199", "Sketch200" section 1 section 2 separate body makes body 154
ref_plane "WorkPlane201" through (89.6, 0, 0) normal (1, 0, 0) x (0, 1, 0)
sketch "Sketch201" plane through (89.6, 0, 0) normal (1, 0, 0) x (0, 0, -1)
  line L0 (20.5, -31) -> (25.5, -31)
  line L1 (25.5, -31) -> (25.5, 31)
  line L2 (25.5, 31) -> (20.5, 31)
  line L3 (20.5, 31) -> (20.5, -31)
ref_plane "WorkPlane202" through (120.4, 0, 0) normal (1, 0, 0) x (0, 1, 0)
sketch "Sketch202" plane through (120.4, 0, 0) normal (1, 0, 0) x (0, 0, -1)
  line L0 (20.5, -30.9848) -> (25.4848, -30.9848)
  line L1 (25.4848, -30.9848) -> (25.4848, 30.9848)
  line L2 (25.4848, 30.9848) -> (20.5, 30.9848)
  line L3 (20.5, 30.9848) -> (20.5, -30.9848)
loft "Loft47" add profiles "Sketch201", "Sketch202" section 1 section 2 separate body makes body 155
ref_plane "WorkPlane203" through (119.6, 0, 0) normal (1, 0, 0) x (0, 1, 0)
sketch "Sketch203" plane through (119.6, 0, 0) normal (1, 0, 0) x (0, 0, -1)
  line L0 (20.5, -31) -> (25.5, -31)
  line L1 (25.5, -31) -> (25.5, 31)
  line L2 (25.5, 31) -> (20.5, 31)
  line L3 (20.5, 31) -> (20.5, -31)
ref_plane "WorkPlane204" through (122.4, 0, 0) normal (1, 0, 0) x (0, 1, 0)
sketch "Sketch204" plane through (122.4, 0, 0) normal (1, 0, 0) x (0, 0, -1)
  line L0 (20.4147, -30.8142) -> (25.323, -30.8142)
  line L1 (25.323, -30.8142) -> (25.323, 30.8142)
  line L2 (25.323, 30.8142) -> (20.4147, 30.8142)
  line L3 (20.4147, 30.8142) -> (20.4147, -30.8142)
loft "Loft48" add profiles "Sketch203", "Sketch204" section 1 section 2 separate body makes body 156
ref_plane "WorkPlane205" through (121.6, 0, 0) normal (1, 0, 0) x (0, 1, 0)
sketch "Sketch205" plane through (121.6, 0, 0) normal (1, 0, 0) x (0, 0, -1)
  line L0 (20.5, -30.939) -> (25.439, -30.939)
  line L1 (25.439, -30.939) -> (25.439, 30.939)
  line L2 (25.439, 30.939) -> (20.5, 30.939)
  line L3 (20.5, 30.939) -> (20.5, -30.939)
ref_plane "WorkPlane206" through (132.0667, 0, 0) normal (1, 0, 0) x (0, 1, 0)
sketch "Sketch206" plane through (132.0667, 0, 0) normal (1, 0, 0) x (0, 0, -1)
  line L0 (18.3534, -28.16) -> (22.8821, -28.16)
  line L1 (22.8821, -28.16) -> (22.8821, 28.16)
  line L2 (22.8821, 28.16) -> (18.3534, 28.16)
  line L3 (18.3534, 28.16) -> (18.3534, -28.16)
loft "Loft49" add profiles "Sketch205", "Sketch206" section 1 section 2 separate body makes body 157
ref_plane "WorkPlane207" through (131.2667, 0, 0) normal (1, 0, 0) x (0, 1, 0)
sketch "Sketch207" plane through (131.2667, 0, 0) normal (1, 0, 0) x (0, 0, -1)
  line L0 (18.524, -28.3803) -> (23.0848, -28.3803)
  line L1 (23.0848, -28.3803) -> (23.0848, 28.3803)
  line L2 (23.0848, 28.3803) -> (18.524, 28.3803)
  line L3 (18.524, 28.3803) -> (18.524, -28.3803)
ref_plane "WorkPlane208" through (143.7333, 0, 0) normal (1, 0, 0) x (0, 1, 0)
sketch "Sketch208" plane through (143.7333, 0, 0) normal (1, 0, 0) x (0, 0, -1)
  line L0 (15.8657, -24.9301) -> (19.9095, -24.9301)
  line L1 (19.9095, -24.9301) -> (19.9095, 24.9301)
  line L2 (19.9095, 24.9301) -> (15.8657, 24.9301)
  line L3 (15.8657, 24.9301) -> (15.8657, -24.9301)
loft "Loft50" add profiles "Sketch207", "Sketch208" section 1 section 2 separate body makes body 158
ref_plane "WorkPlane209" through (142.9333, 0, 0) normal (1, 0, 0) x (0, 1, 0)
sketch "Sketch209" plane through (142.9333, 0, 0) normal (1, 0, 0) x (0, 0, -1)
  line L0 (16.0363, -25.1527) -> (20.1144, -25.1527)
  line L1 (20.1144, -25.1527) -> (20.1144, 25.1527)
  line L2 (20.1144, 25.1527) -> (16.0363, 25.1527)
  line L3 (16.0363, 25.1527) -> (16.0363, -25.1527)
ref_plane "WorkPlane210" through (155.4, 0, 0) normal (1, 0, 0) x (0, 1, 0)
sketch "Sketch210" plane through (155.4, 0, 0) normal (1, 0, 0) x (0, 0, -1)
  line L0 (13.3779, -21.6616) -> (16.8984, -21.6616)
  line L1 (16.8984, -21.6616) -> (16.8984, 21.6616)
  line L2 (16.8984, 21.6616) -> (13.3779, 21.6616)
  line L3 (13.3779, 21.6616) -> (13.3779, -21.6616)
loft "Loft51" add profiles "Sketch209", "Sketch210" section 1 section 2 separate body makes body 159
ref_plane "WorkPlane211" through (154.6, 0, 0) normal (1, 0, 0) x (0, 1, 0)
sketch "Sketch211" plane through (154.6, 0, 0) normal (1, 0, 0) x (0, 0, -1)
  line L0 (13.5485, -21.8873) -> (17.1064, -21.8873)
  line L1 (17.1064, -21.8873) -> (17.1064, 21.8873)
  line L2 (17.1064, 21.8873) -> (13.5485, 21.8873)
  line L3 (13.5485, 21.8873) -> (13.5485, -21.8873)
ref_plane "WorkPlane212" through (167.0667, 0, 0) normal (1, 0, 0) x (0, 1, 0)
sketch "Sketch212" plane through (167.0667, 0, 0) normal (1, 0, 0) x (0, 0, -1)
  line L0 (10.8902, -18.336) -> (13.8302, -18.336)
  line L1 (13.8302, -18.336) -> (13.8302, 18.336)
  line L2 (13.8302, 18.336) -> (10.8902, 18.336)
  line L3 (10.8902, 18.336) -> (10.8902, -18.336)
loft "Loft52" add profiles "Sketch211", "Sketch212" section 1 section 2 separate body makes body 160
ref_plane "WorkPlane213" through (166.2667, 0, 0) normal (1, 0, 0) x (0, 1, 0)
sketch "Sketch213" plane through (166.2667, 0, 0) normal (1, 0, 0) x (0, 0, -1)
  line L0 (11.0608, -18.5666) -> (14.043, -18.5666)
  line L1 (14.043, -18.5666) -> (14.043, 18.5666)
  line L2 (14.043, 18.5666) -> (11.0608, 18.5666)
  line L3 (11.0608, 18.5666) -> (11.0608, -18.5666)
ref_plane "WorkPlane214" through (178.7333, 0, 0) normal (1, 0, 0) x (0, 1, 0)
sketch "Sketch214" plane through (178.7333, 0, 0) normal (1, 0, 0) x (0, 0, -1)
  line L0 (8.4025, -14.9089) -> (10.6604, -14.9089)
  line L1 (10.6604, -14.9089) -> (10.6604, 14.9089)
  line L2 (10.6604, 14.9089) -> (8.4025, 14.9089)
  line L3 (8.4025, 14.9089) -> (8.4025, -14.9089)
loft "Loft53" add profiles "Sketch213", "Sketch214" section 1 section 2 separate body makes body 161
ref_plane "WorkPlane215" through (177.9333, 0, 0) normal (1, 0, 0) x (0, 1, 0)
sketch "Sketch215" plane through (177.9333, 0, 0) normal (1, 0, 0) x (0, 0, -1)
  line L0 (8.573, -15.1492) -> (10.883, -15.1492)
  line L1 (10.883, -15.1492) -> (10.883, 15.1492)
  line L2 (10.883, 15.1492) -> (8.573, 15.1492)
  line L3 (8.573, 15.1492) -> (8.573, -15.1492)
ref_plane "WorkPlane216" through (190, 0, 0) normal (1, 0, 0) x (0, 1, 0)
sketch "Sketch216" plane through (190, 0, 0) normal (1, 0, 0) x (0, 0, -1)
  line L0 (6, -11.2) -> (7.2, -11.2)
  line L1 (7.2, -11.2) -> (7.2, 11.2)
  line L2 (7.2, 11.2) -> (6, 11.2)
  line L3 (6, 11.2) -> (6, -11.2)
loft "Loft54" add profiles "Sketch215", "Sketch216" section 1 section 2 separate body makes body 162
ref_plane "WorkPlane217" through (-30, 0, 0) normal (1, 0, 0) x (0, 1, 0)
sketch "Sketch217" plane through (-30, 0, 0) normal (1, 0, 0) x (0, 0, -1)
  line L0 (-11, 24) -> (11, 24)
  line L1 (11, 24) -> (11, 25.2)
  line L2 (11, 25.2) -> (-11, 25.2)
  line L3 (-11, 25.2) -> (-11, 24)
ref_plane "WorkPlane218" through (-23.6, 0, 0) normal (1, 0, 0) x (0, 1, 0)
sketch "Sketch218" plane through (-23.6, 0, 0) normal (1, 0, 0) x (0, 0, -1)
  line L0 (-13.8, 25.6) -> (13.8, 25.6)
  line L1 (13.8, 25.6) -> (13.8, 29.146)
  line L2 (13.8, 29.146) -> (-13.8, 29.146)
  line L3 (-13.8, 29.146) -> (-13.8, 25.6)
loft "Loft55" add profiles "Sketch217", "Sketch218" section 1 section 2 separate body makes body 163
ref_plane "WorkPlane219" through (-24.4, 0, 0) normal (1, 0, 0) x (0, 1, 0)
sketch "Sketch219" plane through (-24.4, 0, 0) normal (1, 0, 0) x (0, 0, -1)
  line L0 (-13.45, 25.4) -> (13.45, 25.4)
  line L1 (13.45, 25.4) -> (13.45, 28.8108)
  line L2 (13.45, 28.8108) -> (-13.45, 28.8108)
  line L3 (-13.45, 28.8108) -> (-13.45, 25.4)
ref_plane "WorkPlane220" through (-21.6, 0, 0) normal (1, 0, 0) x (0, 1, 0)
sketch "Sketch220" plane through (-21.6, 0, 0) normal (1, 0, 0) x (0, 0, -1)
  line L0 (-14.6091, 26) -> (14.6091, 26)
  line L1 (14.6091, 26) -> (14.6091, 29.8371)
  line L2 (14.6091, 29.8371) -> (-14.6091, 29.8371)
  line L3 (-14.6091, 29.8371) -> (-14.6091, 26)
loft "Loft56" add profiles "Sketch219", "Sketch220" section 1 section 2 separate body makes body 164
ref_plane "WorkPlane221" through (-22.4, 0, 0) normal (1, 0, 0) x (0, 1, 0)
sketch "Sketch221" plane through (-22.4, 0, 0) normal (1, 0, 0) x (0, 0, -1)
  line L0 (-14.325, 25.9) -> (14.325, 25.9)
  line L1 (14.325, 25.9) -> (14.325, 29.6278)
  line L2 (14.325, 29.6278) -> (-14.325, 29.6278)
  line L3 (-14.325, 29.6278) -> (-14.325, 25.9)
ref_plane "WorkPlane222" through (-17.6, 0, 0) normal (1, 0, 0) x (0, 1, 0)
sketch "Sketch222" plane through (-17.6, 0, 0) normal (1, 0, 0) x (0, 0, -1)
  line L0 (-15.7, 26) -> (15.7, 26)
  line L1 (15.7, 26) -> (15.7, 30.2773)
  line L2 (15.7, 30.2773) -> (-15.7, 30.2773)
  line L3 (-15.7, 30.2773) -> (-15.7, 26)
loft "Loft57" add profiles "Sketch221", "Sketch222" section 1 section 2 separate body makes body 165
ref_plane "WorkPlane223" through (-18.4, 0, 0) normal (1, 0, 0) x (0, 1, 0)
sketch "Sketch223" plane through (-18.4, 0, 0) normal (1, 0, 0) x (0, 0, -1)
  line L0 (-15.4818, 26) -> (15.4818, 26)
  line L1 (15.4818, 26) -> (15.4818, 30.2013)
  line L2 (15.4818, 30.2013) -> (-15.4818, 30.2013)
  line L3 (-15.4818, 30.2013) -> (-15.4818, 26)
ref_plane "WorkPlane224" through (-11.6, 0, 0) normal (1, 0, 0) x (0, 1, 0)
sketch "Sketch224" plane through (-11.6, 0, 0) normal (1, 0, 0) x (0, 0, -1)
  line L0 (-17.3364, 26) -> (17.3364, 26)
  line L1 (17.3364, 26) -> (17.3364, 30.7044)
  line L2 (17.3364, 30.7044) -> (-17.3364, 30.7044)
  line L3 (-17.3364, 30.7044) -> (-17.3364, 26)
loft "Loft58" add profiles "Sketch223", "Sketch224" section 1 section 2 separate body makes body 166
ref_plane "WorkPlane225" through (-12.4, 0, 0) normal (1, 0, 0) x (0, 1, 0)
sketch "Sketch225" plane through (-12.4, 0, 0) normal (1, 0, 0) x (0, 0, -1)
  line L0 (-17.1182, 26) -> (17.1182, 26)
  line L1 (17.1182, 26) -> (17.1182, 30.6602)
  line L2 (17.1182, 30.6602) -> (-17.1182, 30.6602)
  line L3 (-17.1182, 30.6602) -> (-17.1182, 26)
ref_plane "WorkPlane226" through (-5.6, 0, 0) normal (1, 0, 0) x (0, 1, 0)
sketch "Sketch226" plane through (-5.6, 0, 0) normal (1, 0, 0) x (0, 0, -1)
  line L0 (-18.9727, 26) -> (18.9727, 26)
  line L1 (18.9727, 26) -> (18.9727, 30.9332)
  line L2 (18.9727, 30.9332) -> (-18.9727, 30.9332)
  line L3 (-18.9727, 30.9332) -> (-18.9727, 26)
loft "Loft59" add profiles "Sketch225", "Sketch226" section 1 section 2 separate body makes body 167
ref_plane "WorkPlane227" through (-6.4, 0, 0) normal (1, 0, 0) x (0, 1, 0)
sketch "Sketch227" plane through (-6.4, 0, 0) normal (1, 0, 0) x (0, 0, -1)
  line L0 (-18.7545, 26) -> (18.7545, 26)
  line L1 (18.7545, 26) -> (18.7545, 30.9125)
  line L2 (18.7545, 30.9125) -> (-18.7545, 30.9125)
  line L3 (-18.7545, 30.9125) -> (-18.7545, 26)
ref_plane "WorkPlane228" through (0.4, 0, 0) normal (1, 0, 0) x (0, 1, 0)
sketch "Sketch228" plane through (0.4, 0, 0) normal (1, 0, 0) x (0, 0, -1)
  line L0 (-20.5, 26) -> (20.5, 26)
  line L1 (20.5, 26) -> (20.5, 31)
  line L2 (20.5, 31) -> (-20.5, 31)
  line L3 (-20.5, 31) -> (-20.5, 26)
loft "Loft60" add profiles "Sketch227", "Sketch228" section 1 section 2 separate body makes body 168
ref_plane "WorkPlane229" through (-0.4, 0, 0) normal (1, 0, 0) x (0, 1, 0)
sketch "Sketch229" plane through (-0.4, 0, 0) normal (1, 0, 0) x (0, 0, -1)
  line L0 (-20.3909, 26) -> (20.3909, 26)
  line L1 (20.3909, 26) -> (20.3909, 30.9997)
  line L2 (20.3909, 30.9997) -> (-20.3909, 30.9997)
  line L3 (-20.3909, 30.9997) -> (-20.3909, 26)
ref_plane "WorkPlane230" through (30.4, 0, 0) normal (1, 0, 0) x (0, 1, 0)
sketch "Sketch230" plane through (30.4, 0, 0) normal (1, 0, 0) x (0, 0, -1)
  line L0 (-20.5, 26) -> (20.5, 26)
  line L1 (20.5, 26) -> (20.5, 31)
  line L2 (20.5, 31) -> (-20.5, 31)
  line L3 (-20.5, 31) -> (-20.5, 26)
loft "Loft61" add profiles "Sketch229", "Sketch230" section 1 section 2 separate body makes body 169
ref_plane "WorkPlane231" through (29.6, 0, 0) normal (1, 0, 0) x (0, 1, 0)
sketch "Sketch231" plane through (29.6, 0, 0) normal (1, 0, 0) x (0, 0, -1)
  line L0 (-20.5, 26) -> (20.5, 26)
  line L1 (20.5, 26) -> (20.5, 31)
  line L2 (20.5, 31) -> (-20.5, 31)
  line L3 (-20.5, 31) -> (-20.5, 26)
ref_plane "WorkPlane232" through (60.4, 0, 0) normal (1, 0, 0) x (0, 1, 0)
sketch "Sketch232" plane through (60.4, 0, 0) normal (1, 0, 0) x (0, 0, -1)
  line L0 (-20.5, 26) -> (20.5, 26)
  line L1 (20.5, 26) -> (20.5, 31)
  line L2 (20.5, 31) -> (-20.5, 31)
  line L3 (-20.5, 31) -> (-20.5, 26)
loft "Loft62" add profiles "Sketch231", "Sketch232" section 1 section 2 separate body makes body 170
ref_plane "WorkPlane233" through (59.6, 0, 0) normal (1, 0, 0) x (0, 1, 0)
sketch "Sketch233" plane through (59.6, 0, 0) normal (1, 0, 0) x (0, 0, -1)
  line L0 (-20.5, 26) -> (20.5, 26)
  line L1 (20.5, 26) -> (20.5, 31)
  line L2 (20.5, 31) -> (-20.5, 31)
  line L3 (-20.5, 31) -> (-20.5, 26)
ref_plane "WorkPlane234" through (90.4, 0, 0) normal (1, 0, 0) x (0, 1, 0)
sketch "Sketch234" plane through (90.4, 0, 0) normal (1, 0, 0) x (0, 0, -1)
  line L0 (-20.5, 26) -> (20.5, 26)
  line L1 (20.5, 26) -> (20.5, 31)
  line L2 (20.5, 31) -> (-20.5, 31)
  line L3 (-20.5, 31) -> (-20.5, 26)
loft "Loft63" add profiles "Sketch233", "Sketch234" section 1 section 2 separate body makes body 171
ref_plane "WorkPlane235" through (89.6, 0, 0) normal (1, 0, 0) x (0, 1, 0)
sketch "Sketch235" plane through (89.6, 0, 0) normal (1, 0, 0) x (0, 0, -1)
  line L0 (-20.5, 26) -> (20.5, 26)
  line L1 (20.5, 26) -> (20.5, 31)
  line L2 (20.5, 31) -> (-20.5, 31)
  line L3 (-20.5, 31) -> (-20.5, 26)
ref_plane "WorkPlane236" through (120.4, 0, 0) normal (1, 0, 0) x (0, 1, 0)
sketch "Sketch236" plane through (120.4, 0, 0) normal (1, 0, 0) x (0, 0, -1)
  line L0 (-20.5, 26) -> (20.5, 26)
  line L1 (20.5, 26) -> (20.5, 30.9848)
  line L2 (20.5, 30.9848) -> (-20.5, 30.9848)
  line L3 (-20.5, 30.9848) -> (-20.5, 26)
loft "Loft64" add profiles "Sketch235", "Sketch236" section 1 section 2 separate body makes body 172
ref_plane "WorkPlane237" through (119.6, 0, 0) normal (1, 0, 0) x (0, 1, 0)
sketch "Sketch237" plane through (119.6, 0, 0) normal (1, 0, 0) x (0, 0, -1)
  line L0 (-20.5, 26) -> (20.5, 26)
  line L1 (20.5, 26) -> (20.5, 31)
  line L2 (20.5, 31) -> (-20.5, 31)
  line L3 (-20.5, 31) -> (-20.5, 26)
ref_plane "WorkPlane238" through (122.4, 0, 0) normal (1, 0, 0) x (0, 1, 0)
sketch "Sketch238" plane through (122.4, 0, 0) normal (1, 0, 0) x (0, 0, -1)
  line L0 (-20.4147, 25.9059) -> (20.4147, 25.9059)
  line L1 (20.4147, 25.9059) -> (20.4147, 30.8142)
  line L2 (20.4147, 30.8142) -> (-20.4147, 30.8142)
  line L3 (-20.4147, 30.8142) -> (-20.4147, 25.9059)
loft "Loft65" add profiles "Sketch237", "Sketch238" section 1 section 2 separate body makes body 173
ref_plane "WorkPlane239" through (121.6, 0, 0) normal (1, 0, 0) x (0, 1, 0)
sketch "Sketch239" plane through (121.6, 0, 0) normal (1, 0, 0) x (0, 0, -1)
  line L0 (-20.5, 26) -> (20.5, 26)
  line L1 (20.5, 26) -> (20.5, 30.939)
  line L2 (20.5, 30.939) -> (-20.5, 30.939)
  line L3 (-20.5, 30.939) -> (-20.5, 26)
ref_plane "WorkPlane240" through (132.0667, 0, 0) normal (1, 0, 0) x (0, 1, 0)
sketch "Sketch240" plane through (132.0667, 0, 0) normal (1, 0, 0) x (0, 0, -1)
  line L0 (-18.3534, 23.6314) -> (18.3534, 23.6314)
  line L1 (18.3534, 23.6314) -> (18.3534, 28.16)
  line L2 (18.3534, 28.16) -> (-18.3534, 28.16)
  line L3 (-18.3534, 28.16) -> (-18.3534, 23.6314)
loft "Loft66" add profiles "Sketch239", "Sketch240" section 1 section 2 separate body makes body 174
ref_plane "WorkPlane241" through (131.2667, 0, 0) normal (1, 0, 0) x (0, 1, 0)
sketch "Sketch241" plane through (131.2667, 0, 0) normal (1, 0, 0) x (0, 0, -1)
  line L0 (-18.524, 23.8196) -> (18.524, 23.8196)
  line L1 (18.524, 23.8196) -> (18.524, 28.3803)
  line L2 (18.524, 28.3803) -> (-18.524, 28.3803)
  line L3 (-18.524, 28.3803) -> (-18.524, 23.8196)
ref_plane "WorkPlane242" through (143.7333, 0, 0) normal (1, 0, 0) x (0, 1, 0)
sketch "Sketch242" plane through (143.7333, 0, 0) normal (1, 0, 0) x (0, 0, -1)
  line L0 (-15.8657, 20.8863) -> (15.8657, 20.8863)
  line L1 (15.8657, 20.8863) -> (15.8657, 24.9301)
  line L2 (15.8657, 24.9301) -> (-15.8657, 24.9301)
  line L3 (-15.8657, 24.9301) -> (-15.8657, 20.8863)
loft "Loft67" add profiles "Sketch241", "Sketch242" section 1 section 2 separate body makes body 175
ref_plane "WorkPlane243" through (142.9333, 0, 0) normal (1, 0, 0) x (0, 1, 0)
sketch "Sketch243" plane through (142.9333, 0, 0) normal (1, 0, 0) x (0, 0, -1)
  line L0 (-16.0363, 21.0745) -> (16.0363, 21.0745)
  line L1 (16.0363, 21.0745) -> (16.0363, 25.1527)
  line L2 (16.0363, 25.1527) -> (-16.0363, 25.1527)
  line L3 (-16.0363, 25.1527) -> (-16.0363, 21.0745)
ref_plane "WorkPlane244" through (155.4, 0, 0) normal (1, 0, 0) x (0, 1, 0)
sketch "Sketch244" plane through (155.4, 0, 0) normal (1, 0, 0) x (0, 0, -1)
  line L0 (-13.3779, 18.1412) -> (13.3779, 18.1412)
  line L1 (13.3779, 18.1412) -> (13.3779, 21.6616)
  line L2 (13.3779, 21.6616) -> (-13.3779, 21.6616)
  line L3 (-13.3779, 21.6616) -> (-13.3779, 18.1412)
loft "Loft68" add profiles "Sketch243", "Sketch244" section 1 section 2 separate body makes body 176
ref_plane "WorkPlane245" through (154.6, 0, 0) normal (1, 0, 0) x (0, 1, 0)
sketch "Sketch245" plane through (154.6, 0, 0) normal (1, 0, 0) x (0, 0, -1)
  line L0 (-13.5485, 18.3294) -> (13.5485, 18.3294)
  line L1 (13.5485, 18.3294) -> (13.5485, 21.8873)
  line L2 (13.5485, 21.8873) -> (-13.5485, 21.8873)
  line L3 (-13.5485, 21.8873) -> (-13.5485, 18.3294)
ref_plane "WorkPlane246" through (167.0667, 0, 0) normal (1, 0, 0) x (0, 1, 0)
sketch "Sketch246" plane through (167.0667, 0, 0) normal (1, 0, 0) x (0, 0, -1)
  line L0 (-10.8902, 15.3961) -> (10.8902, 15.3961)
  line L1 (10.8902, 15.3961) -> (10.8902, 18.336)
  line L2 (10.8902, 18.336) -> (-10.8902, 18.336)
  line L3 (-10.8902, 18.336) -> (-10.8902, 15.3961)
loft "Loft69" add profiles "Sketch245", "Sketch246" section 1 section 2 separate body makes body 177
ref_plane "WorkPlane247" through (166.2667, 0, 0) normal (1, 0, 0) x (0, 1, 0)
sketch "Sketch247" plane through (166.2667, 0, 0) normal (1, 0, 0) x (0, 0, -1)
  line L0 (-11.0608, 15.5843) -> (11.0608, 15.5843)
  line L1 (11.0608, 15.5843) -> (11.0608, 18.5666)
  line L2 (11.0608, 18.5666) -> (-11.0608, 18.5666)
  line L3 (-11.0608, 18.5666) -> (-11.0608, 15.5843)
ref_plane "WorkPlane248" through (178.7333, 0, 0) normal (1, 0, 0) x (0, 1, 0)
sketch "Sketch248" plane through (178.7333, 0, 0) normal (1, 0, 0) x (0, 0, -1)
  line L0 (-8.4025, 12.651) -> (8.4025, 12.651)
  line L1 (8.4025, 12.651) -> (8.4025, 14.9089)
  line L2 (8.4025, 14.9089) -> (-8.4025, 14.9089)
  line L3 (-8.4025, 14.9089) -> (-8.4025, 12.651)
loft "Loft70" add profiles "Sketch247", "Sketch248" section 1 section 2 separate body makes body 178
ref_plane "WorkPlane249" through (177.9333, 0, 0) normal (1, 0, 0) x (0, 1, 0)
sketch "Sketch249" plane through (177.9333, 0, 0) normal (1, 0, 0) x (0, 0, -1)
  line L0 (-8.573, 12.8392) -> (8.573, 12.8392)
  line L1 (8.573, 12.8392) -> (8.573, 15.1492)
  line L2 (8.573, 15.1492) -> (-8.573, 15.1492)
  line L3 (-8.573, 15.1492) -> (-8.573, 12.8392)
ref_plane "WorkPlane250" through (190, 0, 0) normal (1, 0, 0) x (0, 1, 0)
sketch "Sketch250" plane through (190, 0, 0) normal (1, 0, 0) x (0, 0, -1)
  line L0 (-6, 10) -> (6, 10)
  line L1 (6, 10) -> (6, 11.2)
  line L2 (6, 11.2) -> (-6, 11.2)
  line L3 (-6, 11.2) -> (-6, 10)
loft "Loft71" add profiles "Sketch249", "Sketch250" section 1 section 2 separate body makes body 179
ref_plane "WorkPlane251" through (-30, 0, 0) normal (1, 0, 0) x (0, 1, 0)
sketch "Sketch251" plane through (-30, 0, 0) normal (1, 0, 0) x (0, 0, -1)
  line L0 (-11, -25.2) -> (11, -25.2)
  line L1 (11, -25.2) -> (11, -24)
  line L2 (11, -24) -> (-11, -24)
  line L3 (-11, -24) -> (-11, -25.2)
ref_plane "WorkPlane252" through (-23.6, 0, 0) normal (1, 0, 0) x (0, 1, 0)